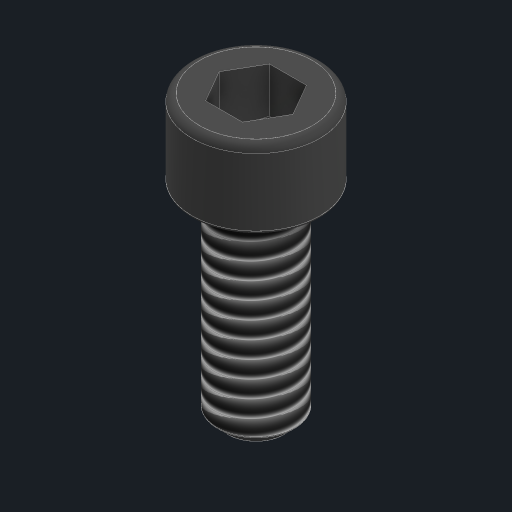
# Autodesk Inventor part: Parafuso Allen Cabeça Cilíndrica, ASME B18.3, 10-24 x 1/2, Aço Liga, Enegrecido de Têmpera
Saved by Autodesk Inventor 2024.3 (Build 283343000, 343)
## iProperties
Created: 2025-07-10
Part Number: Parafuso Allen Cabeça Cilíndrica, ASME B18.3, 10-24 x 1/2, Aço Liga, Enegrecido de Têmpera
Material: Aço, carbono
Document SubType Name: Modeling
Designer: Cliente
Density: 7.85 g/cm^3
Appearance: Aço
Mass: 3.32105 g
Surface Area: 4.36253 cm^2
Volume: 0.423064 cm^3
Author: Cliente
Autodesk Inventor part; units mm, degrees
ref_plane "YZ Plane" through (0, 0, 0) normal (1, 0, 0) x (0, 1, 0)
ref_plane "XZ Plane" through (0, 0, 0) normal (0, 1, 0) x (-1, 0, 0)
ref_plane "XY Plane" through (0, 0, 0) normal (0, 0, 1) x (1, 0, 0)
sketch "Esboço1" plane through (0, 0, 0) normal (0, 0, 1) x (1, 0, 0)
  line L0 (0, 0) -> (0, 4.826)
  line L1 (0, 0) -> (0, -12.7)
  line L2 (0, 4.826) -> (3.5052, 4.826)
  line L3 (3.9624, 4.3688) -> (3.9624, 0.2032)
  arc A0 (3.9624, 4.3688) -> (3.5052, 4.826) centre (3.5052, 4.3688) ccw
  line L4 (0, 0) -> (2.413, 0)
  line L5 (2.413, 0) -> (2.413, -11.9586)
  line L6 (1.6716, -12.7) -> (0, -12.7)
  line L7 (2.413, 0) -> (3.7592, 0)
  arc A1 (3.7592, 0) -> (3.9624, 0.2032) centre (3.7592, 0.2032) ccw
  line L8 (0, 0) -> (2.5654, 0)
  arc A2 (2.5654, 0) -> (2.5241, -0.0761) centre (2.6732, -0.1078) ccw
  line L9 (2.413, 0) -> (2.413, -0.6096)
  line L10 (2.5654, 0) -> (2.6732, 0.1078)
  line L11 (2.5241, -0.0761) -> (2.4162, -0.5836)
  arc A3 (2.4162, -0.5836) -> (2.413, -0.6096) centre (2.5653, -0.6152) ccw
  line L12 (2.3837, -12.0293) -> (1.7423, -12.6707)
  arc A4 (1.6716, -12.7) -> (1.7423, -12.6707) centre (1.6716, -12.6) ccw
  arc A5 (2.3837, -12.0293) -> (2.413, -11.9586) centre (2.313, -11.9586) ccw
  point P0 (3.9624, 4.826)
  point P1 (2.413, -12.7)
  point P2 (2.413, -12)
  point P3 (1.713, -12.7)
  dimension "d0" = 4.826
  dimension "d2" = 12.7
  dimension "d3" = 3.9624
  dimension "d4" = 0.4572
  dimension "d5" = 2.413
  dimension "d6" = 0.2032
  dimension "d7" = 2.5654
  dimension "d8" = 0.1524
  dimension "d9" = 0.6096
  dimension "d10" = 45
  dimension "d12" = 0.1524
  dimension "d13" = 12
  dimension "d14" = 0.7
  dimension "d15" = 0.7
  dimension "d16" = 0.1
  constraints: 26 end point, 12 point on circle, 11 tangent, 9 point on line, 6 centre point, 4 horizontal, 3 perpendicular, 3 vertical, 1 equal radius, 1 vertical alignment
  measures "d0" distance of L0.end L0.start
  measures "d2" distance of L0.start L1.end
  measures "d3" distance of L0.end point (3.962, 4.826)
  measures "d4" radius of A0
  measures "d5" distance of L0.start L4.end
  measures "d6" radius of A1
  measures "d7" distance of L0.start L8.end
  measures "d8" radius of A2
  measures "d9" distance of L4.end L9.end
  measures "d10" angle of L7 L10
  measures "d12" radius of A3
  measures "d13" angle of L9 L11
  measures "d14" distance of point (2.413, -12) point (2.413, -12.7)
  measures "d15" distance of point (1.713, -12.7) point (2.413, -12.7)
  measures "d16" radius of A4
revolve "Revolução1" add sketch "Esboço1" angle 360 about axis through (0, 0, 0) along (0, -1, 0)
thread "Rosca1" size "10-24 UNC" class "2A" standard "ANSI Unified Screw Threads" full length
sketch "Esboço2" plane through (0, 4.826, 0) normal (0, 1, 0) x (1, 0, 0)
  line L0 (2.2914, 0) -> (1.1457, -1.9844)
  line L1 (1.1457, -1.9844) -> (-1.1457, -1.9844)
  line L2 (-1.1457, -1.9844) -> (-2.2914, 0)
  line L3 (-2.2914, 0) -> (-1.1457, 1.9844)
  line L4 (-1.1457, 1.9844) -> (1.1457, 1.9844)
  line L5 (1.1457, 1.9844) -> (2.2914, 0)
  point P0 (0, 0)
  point P1 (0, 0)
  dimension "d20" = 3.9688
  constraints: 12 end point, 1 coincident, 1 horizontal, 13 other
  measures "d20" distance between parallel lines of L1 L4
extrude "Extrusão1" cut sketch "Esboço2" against normal blind 2.8022
sketch "Esboço3" plane through (0, 0, 0) normal (0, 0, 1) x (1, 0, 0)
  line L0 (-1.1457, 2.0238) -> (1.1457, 2.0238) projected
  line L1 (-2.2914, 2.0238) -> (-1.1457, 2.0238) projected
  line L2 (-1.1457, 2.0238) -> (-2.2914, 2.0238) projected
  line L3 (1.1457, 2.0238) -> (-1.1457, 2.0238) projected
  line L4 (2.2914, 2.0238) -> (1.1457, 2.0238) projected
  line L5 (1.1457, 2.0238) -> (2.2914, 2.0238) projected
  line L6 (-2.2914, 2.0238) -> (-0.9721, 1.2621)
  line L7 (-2.2914, 4.826) -> (-1.1457, 4.826) projected
  line L8 (-2.2914, 4.826) -> (-2.2914, 2.0238) projected
  line L9 (-2.2914, 2.0238) -> (-1.1457, 2.0238) projected
  line L10 (-1.1457, 4.826) -> (-1.1457, 2.0238) projected
  line L11 (1.1457, 4.826) -> (2.2914, 4.826) projected
  line L12 (1.1457, 4.826) -> (1.1457, 2.0238) projected
  line L13 (1.1457, 2.0238) -> (2.2914, 2.0238) projected
  line L14 (2.2914, 4.826) -> (2.2914, 2.0238) projected
  arc A0 (-2.2914, 2.0238) -> (2.2914, 2.0238) centre (0, 5.9926) ccw
  line L15 (0, 1.4098) -> (0, 2.0238)
  point P0 (0, 0)
  dimension "d23" = 120
  constraints: 4 end point, 3 point on circle, 1 centre point, 1 midpoint, 1 tangent
  measures "d23" angle of L6 L8
revolve "Revolução2" cut sketch "Esboço3" angle 360 about axis through (0, 1.4098, 0) along (0, 1, 0) contours L0 L15 A0 L1
sketch "Esboço4" plane through (0, 4.826, 0) normal (0, 1, 0) x (1, 0, 0)
  line L0 (-2.2914, 0) -> (-1.1457, 1.9844) projected
  line L1 (-1.1457, 1.9844) -> (1.1457, 1.9844) projected
  line L2 (1.1457, 1.9844) -> (2.2914, 0) projected
  line L3 (2.2914, 0) -> (1.1457, -1.9844) projected
  line L4 (1.1457, -1.9844) -> (-1.1457, -1.9844) projected
  line L5 (-1.1457, -1.9844) -> (-2.2914, 0) projected
  circle A0 centre (0, 0) radius 3.5052 projected
extrude "Extrusão2" add sketch "Esboço4" against normal blind 4
equation "\"d12\" = d8"
equation "\"d15\" = d14"
